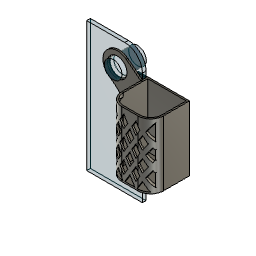
board pen holder side v5 (Autodesk Fusion 360 design; units mm, degrees)
Autodesk Fusion 360 part; units mm, degrees
sketch "Sketch1" plane through (0, 0, 0) normal (0, 1, 0) x (1, 0, 0)
  line L0 (0, 0) -> (-60, 0) construction
  line L1 (-60, 0) -> (-60, 140) construction
  line L2 (-60, 140) -> (0, 140) construction
  line L3 (0, 140) -> (0, 0) construction
  circle A0 centre (-19, 19) radius 19
  line L4 (-60, 0) -> (-19, 0)
  line L5 (0, 140) -> (0, 19)
  line L6 (-60, 0) -> (-60, 140)
  line L7 (-60, 140) -> (0, 140)
  line L8 (0, 0) -> (-34.8, 0) construction
  line L9 (-34.8, 0) -> (-34.8, 34.8) construction
  line L10 (-34.8, 34.8) -> (0, 34.8) construction
  line L11 (0, 34.8) -> (0, 0) construction
  circle A1 centre (-25.3, 25.3) radius 9.5
  dimension "d1" = 60
  dimension "d2" = 140
  dimension "d3" = 19
  dimension "d4" = 34.8
  dimension "d5" = 34.8
  dimension "d6" = 9.5
  constraint horizontal L0
  constraint vertical L1
  constraint horizontal L2
  constraint vertical L3
  constraint coincident L0.start L3.end
  constraint tangent L0 A0
  constraint tangent L3 A0
  constraint coincident A0 L4.end
  constraint tangent A0 L4
  constraint coincident A0 L5.end
  constraint tangent A0 L5
  constraint horizontal L8
  constraint vertical L9
  constraint horizontal L10
  constraint vertical L11
  constraint tangent L9 A1
  constraint tangent L10 A1
  measures "d1" distance of L0.start L0.end
  measures "d2" distance of L0.start L2.end
  measures "d3" radius of A0
  measures "d4" distance of L0.start L8.end
  measures "d5" distance of L0.start L10.end
  measures "d6" radius of A1
extrude "Extrude1" add sketch "Sketch1" along normal blind 3.95 makes body 1
extrude "Extrude2" add sketch "Sketch1" against normal blind 6.2 separate body contours A1 makes body 2
extrude "Extrude3" add sketch "Sketch1" along normal blind 20 contours A1 bodies 1 2
copy_body "Body->Comp1" bodies 1 removing the originals makes body 3 in component "Glass Board"
sketch "Sketch1 (2)" plane through (0, 0, 0) normal (0, -1, 0) x (1, 0, 0) in component "Holder"
  circle A0 centre (-25.3, -25.3) radius 9.5
  line L0 (-19, 0) -> (-60, 0)
  line L1 (-60, 0) -> (-60, -140)
  line L2 (-60, -140) -> (0, -140)
  line L3 (0, -140) -> (0, -19)
  arc A1 (0, -19) -> (-19, 0) centre (-19, -19) ccw
  circle A2 centre (-25.3, -25.3) radius 10.5
  circle A3 centre (-25.3, -25.3) radius 15.5
  line L4 (-25.3, -25.3) -> (0, -25.3) construction
  line L5 (0, -25.3) -> (-15.804, -13.0495)
  line L6 (-34.796, -37.5505) -> (-27.6206, -43.1126)
  line L7 (-16, -66.8233) -> (-16, -140) construction
  line L8 (-60, -95.3) -> (100, -95.3) construction
  line L9 (0, -25.3) -> (1.75, -25.3)
  line L10 (1.75, -25.3) -> (1.75, -95.3)
  line L11 (1.75, -95.3) -> (0, -95.3)
  line L12 (0, -95.3) -> (0, -25.3) construction
  line L13 (1.75, -25.3) -> (45, -25.3)
  line L14 (45, -25.3) -> (45, -95.3)
  line L15 (45, -95.3) -> (1.75, -95.3)
  line L16 (1.75, -95.3) -> (1.75, -25.3)
  arc A4 (-16, -66.8233) -> (-27.6206, -43.1126) centre (-46, -66.8233) ccw
  line L17 (-16, -66.8233) -> (-16, -95.3) construction
  line L18 (-16, -66.8233) -> (-16, -95.3)
  line L19 (-16, -95.3) -> (0, -95.3)
  line L20 (0, -95.3) -> (0, -25.3)
  line L21 (-16, -95.3) -> (0, -95.3)
  line L22 (0, -95.3) -> (0, -25.3)
  line L23 (0, -25.3) -> (-16, -25.3)
  line L24 (-16, -25.3) -> (-16, -95.3)
  line L25 (45, -25.3) -> (43.25, -25.3)
  line L26 (43.25, -25.3) -> (43.25, -95.3)
  line L27 (43.25, -95.3) -> (45, -95.3)
  line L28 (45, -95.3) -> (45, -25.3)
  line L29 (1.75, -95.3) -> (43.25, -95.3)
  line L30 (43.25, -95.3) -> (43.25, -93.55)
  line L31 (43.25, -93.55) -> (1.75, -93.55)
  line L32 (1.75, -93.55) -> (1.75, -95.3)
  dimension "d13" = 1
  dimension "d14" = 5
  dimension "d15" = 16
  dimension "d16" = 70
  dimension "d17" = 1.75
  dimension "d18" = 45
  dimension "d19" = 160
  dimension "d20" = 30
  dimension "d33" = 1.75
  dimension "d34" = 1.75
  constraint concentric A0 A2
  constraint concentric A2 A3
  constraint coincident A0.centre A2.centre
  constraint coincident L3 L4.end
  constraint perpendicular L3 L4
  constraint coincident A3 L5.end
  constraint tangent A3 L5
  constraint coincident A3 L6.start
  constraint parallel L5 L6
  constraint tangent A3 L6
  constraint coincident L2 L7.end
  constraint perpendicular L2 L7
  constraint coincident L1 L8.start
  constraint perpendicular L3 L8
  constraint horizontal L9
  constraint vertical L10
  constraint horizontal L11
  constraint vertical L12
  constraint coincident L8 L10.end
  constraint horizontal L13
  constraint vertical L14
  constraint horizontal L15
  constraint vertical L16
  constraint coincident L8 L14.end
  constraint tangent L6 A4
  constraint tangent L7 A4
  constraint coincident L7 L17.end
  constraint coincident L8 L17.end
  constraint horizontal L21
  constraint vertical L22
  constraint horizontal L23
  constraint vertical L24
  constraint horizontal L25
  constraint vertical L26
  constraint horizontal L27
  constraint vertical L28
  constraint coincident L8 L26.end
  constraint horizontal L29
  constraint vertical L30
  constraint horizontal L31
  constraint vertical L32
  constraint coincident L26 L30.end
  measures "d13" distance of A0 A2
  measures "d14" distance of A2 A3
  measures "d15" distance of L3 L7
  measures "d16" distance of L4.end L8
  measures "d17" distance of L10 L12
  measures "d18" distance of L3 L14
  measures "d19" distance of L8.start L8.end
  measures "d20" radius of A4
  measures "d33" distance of L26 L28
  measures "d34" distance of L29 L31
extrude "Extrude1'" add sketch "Sketch1 (2)" along normal blind 1.75 separate body contours A2 A3 L23 L24 | A2 A3 L23 L24 | L3 A3 L18 L19 L20 L21 L22 L23 L24 | A3 L5 L23 | A3 L6 A4 L24 makes body 4 in component "Holder"
extrude "Extrude2'" add sketch "Sketch1 (2)" against normal blind 1.75 from surface at -3.95 separate body contours L3 A3 L18 L19 L20 L21 L22 L23 L24 makes body 5 in component "Holder"
extrude "Extrude3'" add sketch "Sketch1 (2)" against normal up to surface (7.45 mm away) from surface at 1.75 contours L3 L9 L10 L11 L16 L20 L22 L32 bodies 4 5 in component "Holder"
extrude "Extrude4" add sketch "Sketch1 (2)" along normal blind 1.75 from surface at -5.7 contours L10 L13 L16 L26 L31 | L10 L15 L16 L26 L29 L30 L31 L32 | L13 L14 L15 L25 L26 L27 L28 L30 bodies 4 in component "Holder"
extrude "Extrude5" add sketch "Sketch1 (2)" along normal blind 40 from surface at -3.95 contours L10 L15 L16 L26 L29 L30 L31 L32 | L13 L14 L15 L25 L26 L27 L28 L30 bodies 4 in component "Holder"
extrude "Extrude6" add sketch "Sketch1 (2)" along normal up to surface (36.05 mm away) contours L3 L9 L10 L11 L16 L20 L22 L32 bodies 4 in component "Holder"
extrude "Extrude7" add sketch "Sketch1 (2)" against normal blind 1.75 from surface at 36.05 contours L10 L13 L16 L26 L31 bodies 4 in component "Holder"
sketch "Sketch2" plane through (0, -34.3, 0) normal (0, 1, 0) x (-1, 0, 0) in component "Holder"
  line L0 (-43.25, -93.55) -> (-1.75, -93.55)
  line L1 (-1.75, -93.55) -> (-1.75, -25.3)
  line L2 (-1.75, -25.3) -> (-43.25, -25.3)
  line L3 (-43.25, -25.3) -> (-43.25, -93.55)
  line L4 (-40.2857, -28.3) -> (-43.25, -34.0813) construction
  line L5 (-43.25, -34.0813) -> (-40.2857, -39.8625) construction
  line L6 (-40.2857, -39.8625) -> (-37.3214, -34.0813) construction
  line L7 (-37.3214, -34.0813) -> (-40.2857, -28.3) construction
  line L8 (-40.2857, -28.3) -> (-40.2857, -39.8625) construction
  line L9 (-43.25, -25.3) -> (-1.75, -25.3) construction
  line L10 (-1.75, -25.3) -> (-1.75, -28.3) construction
  line L11 (-1.75, -28.3) -> (-43.25, -28.3) construction
  line L12 (-43.25, -28.3) -> (-43.25, -25.3) construction
  line L13 (-43.25, -93.55) -> (-1.75, -93.55) construction
  line L14 (-1.75, -93.55) -> (-1.75, -90.55) construction
  line L15 (-1.75, -90.55) -> (-43.25, -90.55) construction
  line L16 (-43.25, -90.55) -> (-43.25, -93.55) construction
  line L17 (-64, -28.3) -> (-66.9643, -34.0813)
  line L18 (-66.9643, -34.0813) -> (-64, -39.8625)
  line L19 (-64, -39.8625) -> (-61.0357, -34.0813)
  line L20 (-61.0357, -34.0813) -> (-64, -28.3)
  line L21 (-58.0714, -28.3) -> (-61.0357, -34.0813)
  line L22 (-61.0357, -34.0813) -> (-58.0714, -39.8625)
  line L23 (-58.0714, -39.8625) -> (-55.1071, -34.0813)
  line L24 (-55.1071, -34.0813) -> (-58.0714, -28.3)
  line L25 (-52.1429, -28.3) -> (-55.1071, -34.0813)
  line L26 (-55.1071, -34.0813) -> (-52.1429, -39.8625)
  line L27 (-52.1429, -39.8625) -> (-49.1786, -34.0813)
  line L28 (-49.1786, -34.0813) -> (-52.1429, -28.3)
  line L29 (-46.2143, -28.3) -> (-49.1786, -34.0813)
  line L30 (-49.1786, -34.0813) -> (-46.2143, -39.8625)
  line L31 (-46.2143, -39.8625) -> (-43.25, -34.0813)
  line L32 (-43.25, -34.0813) -> (-46.2143, -28.3)
  line L33 (-34.3571, -28.3) -> (-37.3214, -34.0813)
  line L34 (-37.3214, -34.0813) -> (-34.3571, -39.8625)
  line L35 (-34.3571, -39.8625) -> (-31.3929, -34.0813)
  line L36 (-31.3929, -34.0813) -> (-34.3571, -28.3)
  line L37 (-28.4286, -28.3) -> (-31.3929, -34.0813)
  line L38 (-31.3929, -34.0813) -> (-28.4286, -39.8625)
  line L39 (-28.4286, -39.8625) -> (-25.4643, -34.0813)
  line L40 (-25.4643, -34.0813) -> (-28.4286, -28.3)
  line L41 (-22.5, -28.3) -> (-25.4643, -34.0813)
  line L42 (-25.4643, -34.0813) -> (-22.5, -39.8625)
  line L43 (-22.5, -39.8625) -> (-19.5357, -34.0813)
  line L44 (-19.5357, -34.0813) -> (-22.5, -28.3)
  line L45 (-64, -39.8625) -> (-66.9643, -45.6438)
  line L46 (-66.9643, -45.6438) -> (-64, -51.425)
  line L47 (-64, -51.425) -> (-61.0357, -45.6438)
  line L48 (-61.0357, -45.6438) -> (-64, -39.8625)
  line L49 (-58.0714, -39.8625) -> (-61.0357, -45.6438)
  line L50 (-61.0357, -45.6438) -> (-58.0714, -51.425)
  line L51 (-58.0714, -51.425) -> (-55.1071, -45.6438)
  line L52 (-55.1071, -45.6438) -> (-58.0714, -39.8625)
  line L53 (-52.1429, -39.8625) -> (-55.1071, -45.6438)
  line L54 (-55.1071, -45.6438) -> (-52.1429, -51.425)
  line L55 (-52.1429, -51.425) -> (-49.1786, -45.6438)
  line L56 (-49.1786, -45.6438) -> (-52.1429, -39.8625)
  line L57 (-46.2143, -39.8625) -> (-49.1786, -45.6438)
  line L58 (-49.1786, -45.6438) -> (-46.2143, -51.425)
  line L59 (-46.2143, -51.425) -> (-43.25, -45.6438)
  line L60 (-43.25, -45.6438) -> (-46.2143, -39.8625)
  line L61 (-40.2857, -39.8625) -> (-43.25, -45.6438)
  line L62 (-43.25, -45.6438) -> (-40.2857, -51.425)
  line L63 (-40.2857, -51.425) -> (-37.3214, -45.6438)
  line L64 (-37.3214, -45.6438) -> (-40.2857, -39.8625)
  line L65 (-34.3571, -39.8625) -> (-37.3214, -45.6438)
  line L66 (-37.3214, -45.6438) -> (-34.3571, -51.425)
  line L67 (-34.3571, -51.425) -> (-31.3929, -45.6438)
  line L68 (-31.3929, -45.6438) -> (-34.3571, -39.8625)
  line L69 (-28.4286, -39.8625) -> (-31.3929, -45.6438)
  line L70 (-31.3929, -45.6438) -> (-28.4286, -51.425)
  line L71 (-28.4286, -51.425) -> (-25.4643, -45.6438)
  line L72 (-25.4643, -45.6438) -> (-28.4286, -39.8625)
  line L73 (-22.5, -39.8625) -> (-25.4643, -45.6438)
  line L74 (-25.4643, -45.6438) -> (-22.5, -51.425)
  line L75 (-22.5, -51.425) -> (-19.5357, -45.6438)
  line L76 (-19.5357, -45.6438) -> (-22.5, -39.8625)
  line L77 (-64, -51.425) -> (-66.9643, -57.2063)
  line L78 (-66.9643, -57.2063) -> (-64, -62.9875)
  line L79 (-64, -62.9875) -> (-61.0357, -57.2063)
  line L80 (-61.0357, -57.2063) -> (-64, -51.425)
  line L81 (-58.0714, -51.425) -> (-61.0357, -57.2063)
  line L82 (-61.0357, -57.2063) -> (-58.0714, -62.9875)
  line L83 (-58.0714, -62.9875) -> (-55.1071, -57.2063)
  line L84 (-55.1071, -57.2063) -> (-58.0714, -51.425)
  line L85 (-52.1429, -51.425) -> (-55.1071, -57.2063)
  line L86 (-55.1071, -57.2063) -> (-52.1429, -62.9875)
  line L87 (-52.1429, -62.9875) -> (-49.1786, -57.2063)
  line L88 (-49.1786, -57.2063) -> (-52.1429, -51.425)
  line L89 (-46.2143, -51.425) -> (-49.1786, -57.2063)
  line L90 (-49.1786, -57.2063) -> (-46.2143, -62.9875)
  line L91 (-46.2143, -62.9875) -> (-43.25, -57.2063)
  line L92 (-43.25, -57.2063) -> (-46.2143, -51.425)
  line L93 (-40.2857, -51.425) -> (-43.25, -57.2063)
  line L94 (-43.25, -57.2063) -> (-40.2857, -62.9875)
  line L95 (-40.2857, -62.9875) -> (-37.3214, -57.2063)
  line L96 (-37.3214, -57.2063) -> (-40.2857, -51.425)
  line L97 (-34.3571, -51.425) -> (-37.3214, -57.2063)
  line L98 (-37.3214, -57.2063) -> (-34.3571, -62.9875)
  line L99 (-34.3571, -62.9875) -> (-31.3929, -57.2063)
  line L100 (-31.3929, -57.2063) -> (-34.3571, -51.425)
  line L101 (-28.4286, -51.425) -> (-31.3929, -57.2063)
  line L102 (-31.3929, -57.2063) -> (-28.4286, -62.9875)
  line L103 (-28.4286, -62.9875) -> (-25.4643, -57.2063)
  line L104 (-25.4643, -57.2063) -> (-28.4286, -51.425)
  line L105 (-22.5, -51.425) -> (-25.4643, -57.2063)
  line L106 (-25.4643, -57.2063) -> (-22.5, -62.9875)
  line L107 (-22.5, -62.9875) -> (-19.5357, -57.2063)
  line L108 (-19.5357, -57.2063) -> (-22.5, -51.425)
  line L109 (-64, -62.9875) -> (-66.9643, -68.7688)
  line L110 (-66.9643, -68.7688) -> (-64, -74.55)
  line L111 (-64, -74.55) -> (-61.0357, -68.7688)
  line L112 (-61.0357, -68.7688) -> (-64, -62.9875)
  line L113 (-58.0714, -62.9875) -> (-61.0357, -68.7688)
  line L114 (-61.0357, -68.7688) -> (-58.0714, -74.55)
  line L115 (-58.0714, -74.55) -> (-55.1071, -68.7688)
  line L116 (-55.1071, -68.7688) -> (-58.0714, -62.9875)
  line L117 (-52.1429, -62.9875) -> (-55.1071, -68.7688)
  line L118 (-55.1071, -68.7688) -> (-52.1429, -74.55)
  line L119 (-52.1429, -74.55) -> (-49.1786, -68.7688)
  line L120 (-49.1786, -68.7688) -> (-52.1429, -62.9875)
  line L121 (-46.2143, -62.9875) -> (-49.1786, -68.7688)
  line L122 (-49.1786, -68.7688) -> (-46.2143, -74.55)
  line L123 (-46.2143, -74.55) -> (-43.25, -68.7688)
  line L124 (-43.25, -68.7688) -> (-46.2143, -62.9875)
  line L125 (-40.2857, -62.9875) -> (-43.25, -68.7688)
  line L126 (-43.25, -68.7688) -> (-40.2857, -74.55)
  line L127 (-40.2857, -74.55) -> (-37.3214, -68.7688)
  line L128 (-37.3214, -68.7688) -> (-40.2857, -62.9875)
  line L129 (-34.3571, -62.9875) -> (-37.3214, -68.7688)
  line L130 (-37.3214, -68.7688) -> (-34.3571, -74.55)
  line L131 (-34.3571, -74.55) -> (-31.3929, -68.7688)
  line L132 (-31.3929, -68.7688) -> (-34.3571, -62.9875)
  line L133 (-28.4286, -62.9875) -> (-31.3929, -68.7688)
  line L134 (-31.3929, -68.7688) -> (-28.4286, -74.55)
  line L135 (-28.4286, -74.55) -> (-25.4643, -68.7688)
  line L136 (-25.4643, -68.7688) -> (-28.4286, -62.9875)
  line L137 (-22.5, -62.9875) -> (-25.4643, -68.7688)
  line L138 (-25.4643, -68.7688) -> (-22.5, -74.55)
  line L139 (-22.5, -74.55) -> (-19.5357, -68.7688)
  line L140 (-19.5357, -68.7688) -> (-22.5, -62.9875)
  line L141 (-64, -74.55) -> (-66.9643, -80.3313)
  line L142 (-66.9643, -80.3313) -> (-64, -86.1125)
  line L143 (-64, -86.1125) -> (-61.0357, -80.3313)
  line L144 (-61.0357, -80.3313) -> (-64, -74.55)
  line L145 (-58.0714, -74.55) -> (-61.0357, -80.3313)
  line L146 (-61.0357, -80.3313) -> (-58.0714, -86.1125)
  line L147 (-58.0714, -86.1125) -> (-55.1071, -80.3313)
  line L148 (-55.1071, -80.3313) -> (-58.0714, -74.55)
  line L149 (-52.1429, -74.55) -> (-55.1071, -80.3313)
  line L150 (-55.1071, -80.3313) -> (-52.1429, -86.1125)
  line L151 (-52.1429, -86.1125) -> (-49.1786, -80.3313)
  line L152 (-49.1786, -80.3313) -> (-52.1429, -74.55)
  line L153 (-46.2143, -74.55) -> (-49.1786, -80.3313)
  line L154 (-49.1786, -80.3313) -> (-46.2143, -86.1125)
  line L155 (-46.2143, -86.1125) -> (-43.25, -80.3313)
  line L156 (-43.25, -80.3313) -> (-46.2143, -74.55)
  line L157 (-40.2857, -74.55) -> (-43.25, -80.3313)
  line L158 (-43.25, -80.3313) -> (-40.2857, -86.1125)
  line L159 (-40.2857, -86.1125) -> (-37.3214, -80.3313)
  line L160 (-37.3214, -80.3313) -> (-40.2857, -74.55)
  line L161 (-34.3571, -74.55) -> (-37.3214, -80.3313)
  line L162 (-37.3214, -80.3313) -> (-34.3571, -86.1125)
  line L163 (-34.3571, -86.1125) -> (-31.3929, -80.3313)
  line L164 (-31.3929, -80.3313) -> (-34.3571, -74.55)
  line L165 (-28.4286, -74.55) -> (-31.3929, -80.3313)
  line L166 (-31.3929, -80.3313) -> (-28.4286, -86.1125)
  line L167 (-28.4286, -86.1125) -> (-25.4643, -80.3313)
  line L168 (-25.4643, -80.3313) -> (-28.4286, -74.55)
  line L169 (-22.5, -74.55) -> (-25.4643, -80.3313)
  line L170 (-25.4643, -80.3313) -> (-22.5, -86.1125)
  line L171 (-22.5, -86.1125) -> (-19.5357, -80.3313)
  line L172 (-19.5357, -80.3313) -> (-22.5, -74.55)
  line L173 (-43.25, -34.0813) -> (-37.3214, -34.0813) construction
  line L174 (-16.5714, -28.3) -> (-19.5357, -34.0813)
  line L175 (-19.5357, -34.0813) -> (-16.5714, -39.8625)
  line L176 (-16.5714, -39.8625) -> (-13.6071, -34.0813)
  line L177 (-13.6071, -34.0813) -> (-16.5714, -28.3)
  line L178 (-10.6429, -28.3) -> (-13.6071, -34.0813)
  line L179 (-13.6071, -34.0813) -> (-10.6429, -39.8625)
  line L180 (-10.6429, -39.8625) -> (-7.6786, -34.0813)
  line L181 (-7.6786, -34.0813) -> (-10.6429, -28.3)
  line L182 (-16.5714, -39.8625) -> (-19.5357, -45.6438)
  line L183 (-19.5357, -45.6438) -> (-16.5714, -51.425)
  line L184 (-16.5714, -51.425) -> (-13.6071, -45.6438)
  line L185 (-13.6071, -45.6438) -> (-16.5714, -39.8625)
  line L186 (-10.6429, -39.8625) -> (-13.6071, -45.6438)
  line L187 (-13.6071, -45.6438) -> (-10.6429, -51.425)
  line L188 (-10.6429, -51.425) -> (-7.6786, -45.6438)
  line L189 (-7.6786, -45.6438) -> (-10.6429, -39.8625)
  line L190 (-16.5714, -51.425) -> (-19.5357, -57.2063)
  line L191 (-19.5357, -57.2063) -> (-16.5714, -62.9875)
  line L192 (-16.5714, -62.9875) -> (-13.6071, -57.2063)
  line L193 (-13.6071, -57.2063) -> (-16.5714, -51.425)
  line L194 (-10.6429, -51.425) -> (-13.6071, -57.2063)
  line L195 (-13.6071, -57.2063) -> (-10.6429, -62.9875)
  line L196 (-10.6429, -62.9875) -> (-7.6786, -57.2063)
  line L197 (-7.6786, -57.2063) -> (-10.6429, -51.425)
  line L198 (-16.5714, -62.9875) -> (-19.5357, -68.7688)
  line L199 (-19.5357, -68.7688) -> (-16.5714, -74.55)
  line L200 (-16.5714, -74.55) -> (-13.6071, -68.7688)
  line L201 (-13.6071, -68.7688) -> (-16.5714, -62.9875)
  line L202 (-10.6429, -62.9875) -> (-13.6071, -68.7688)
  line L203 (-13.6071, -68.7688) -> (-10.6429, -74.55)
  line L204 (-10.6429, -74.55) -> (-7.6786, -68.7688)
  line L205 (-7.6786, -68.7688) -> (-10.6429, -62.9875)
  line L206 (-16.5714, -74.55) -> (-19.5357, -80.3313)
  line L207 (-19.5357, -80.3313) -> (-16.5714, -86.1125)
  line L208 (-16.5714, -86.1125) -> (-13.6071, -80.3313)
  line L209 (-13.6071, -80.3313) -> (-16.5714, -74.55)
  line L210 (-10.6429, -74.55) -> (-13.6071, -80.3313)
  line L211 (-13.6071, -80.3313) -> (-10.6429, -86.1125)
  line L212 (-10.6429, -86.1125) -> (-7.6786, -80.3313)
  line L213 (-7.6786, -80.3313) -> (-10.6429, -74.55)
  line L214 (-64, -86.1125) -> (-66.9643, -91.8938)
  line L215 (-66.9643, -91.8938) -> (-64, -97.675)
  line L216 (-64, -97.675) -> (-61.0357, -91.8938)
  line L217 (-61.0357, -91.8938) -> (-64, -86.1125)
  line L218 (-58.0714, -86.1125) -> (-61.0357, -91.8938)
  line L219 (-61.0357, -91.8938) -> (-58.0714, -97.675)
  line L220 (-58.0714, -97.675) -> (-55.1071, -91.8938)
  line L221 (-55.1071, -91.8938) -> (-58.0714, -86.1125)
  line L222 (-52.1429, -86.1125) -> (-55.1071, -91.8938)
  line L223 (-55.1071, -91.8938) -> (-52.1429, -97.675)
  line L224 (-52.1429, -97.675) -> (-49.1786, -91.8938)
  line L225 (-49.1786, -91.8938) -> (-52.1429, -86.1125)
  line L226 (-46.2143, -86.1125) -> (-49.1786, -91.8938)
  line L227 (-49.1786, -91.8938) -> (-46.2143, -97.675)
  line L228 (-46.2143, -97.675) -> (-43.25, -91.8938)
  line L229 (-43.25, -91.8938) -> (-46.2143, -86.1125)
  line L230 (-40.2857, -86.1125) -> (-43.25, -91.8938)
  line L231 (-43.25, -91.8938) -> (-40.2857, -97.675)
  line L232 (-40.2857, -97.675) -> (-37.3214, -91.8938)
  line L233 (-37.3214, -91.8938) -> (-40.2857, -86.1125)
  line L234 (-34.3571, -86.1125) -> (-37.3214, -91.8938)
  line L235 (-37.3214, -91.8938) -> (-34.3571, -97.675)
  line L236 (-34.3571, -97.675) -> (-31.3929, -91.8938)
  line L237 (-31.3929, -91.8938) -> (-34.3571, -86.1125)
  line L238 (-28.4286, -86.1125) -> (-31.3929, -91.8938)
  line L239 (-31.3929, -91.8938) -> (-28.4286, -97.675)
  line L240 (-28.4286, -97.675) -> (-25.4643, -91.8938)
  line L241 (-25.4643, -91.8938) -> (-28.4286, -86.1125)
  line L242 (-22.5, -86.1125) -> (-25.4643, -91.8938)
  line L243 (-25.4643, -91.8938) -> (-22.5, -97.675)
  line L244 (-22.5, -97.675) -> (-19.5357, -91.8938)
  line L245 (-19.5357, -91.8938) -> (-22.5, -86.1125)
  line L246 (-16.5714, -86.1125) -> (-19.5357, -91.8938)
  line L247 (-19.5357, -91.8938) -> (-16.5714, -97.675)
  line L248 (-16.5714, -97.675) -> (-13.6071, -91.8938)
  line L249 (-13.6071, -91.8938) -> (-16.5714, -86.1125)
  line L250 (-10.6429, -86.1125) -> (-13.6071, -91.8938)
  line L251 (-13.6071, -91.8938) -> (-10.6429, -97.675)
  line L252 (-10.6429, -97.675) -> (-7.6786, -91.8938)
  line L253 (-7.6786, -91.8938) -> (-10.6429, -86.1125)
  line L254 (-40.2857, -38.7666) -> (-37.8833, -34.0813)
  line L255 (-37.8833, -34.0813) -> (-40.2857, -29.3959)
  line L256 (-40.2857, -29.3959) -> (-42.6881, -34.0813)
  line L257 (-42.6881, -34.0813) -> (-40.2857, -38.7666)
  dimension "d43" = 11.5625
  dimension "d44" = 68.25
  dimension "d45" = 3
  dimension "d46" = 3
  dimension "d47" = 62.25
  dimension "d50" = 5.9286
  dimension "d51" = -11.5625
  dimension "d53" = 5.9286
  dimension "d54" = 41.5
  dimension "d55" = -0.5
  constraint parallel L5 L7
  constraint parallel L4 L6
  constraint equal L4 L7
  constraint vertical L8
  constraint horizontal L9
  constraint vertical L10
  constraint horizontal L11
  constraint vertical L12
  constraint coincident L1 L10.end
  constraint coincident L2.end L3.start
  constraint horizontal L13
  constraint vertical L14
  constraint horizontal L15
  constraint vertical L16
  constraint coincident L1 L14.end
  constraint coincident L0.start L3.end
  constraint coincident L4.start L11
  constraint coincident L3 L4.end
  measures "d43" distance of L4.start L5.end
  measures "d44" distance of L0.start L2.end
  measures "d45" distance of L2.end L11.end
  measures "d46" distance of L0.start L15.end
  measures "d47" distance of L11 L15
  measures "d53" distance of L4.end L6.end
  measures "d54" distance of L2.end L1.end
sketch "Sketch2 (2)" plane through (0, -34.3, 0) normal (0, 1, 0) x (-1, 0, 0)
  line L0 (-43.25, -93.55) -> (-1.75, -93.55)
  line L1 (-1.75, -93.55) -> (-1.75, -24.2469)
  line L2 (-1.75, -25.3) -> (-43.25, -25.3)
  line L3 (-43.25, -25.3) -> (-43.25, -93.55)
  line L4 (-43.8699, -94.5785) -> (-0.6794, -23.5392) construction
  line L5 (-42.1609, -95.6175) -> (1.0295, -24.5782)
  line L6 (-45.5788, -93.5395) -> (-2.3884, -22.5002)
  line L7 (-22.5, -25.3) -> (-22.5, -93.55) construction
  line L8 (0.5788, -93.5395) -> (-42.6116, -22.5002)
  line L9 (-2.8391, -95.6175) -> (-46.0295, -24.5782)
  line L10 (-71.5788, -93.5395) -> (-28.3884, -22.5002)
  line L11 (-68.1609, -95.6175) -> (-24.9705, -24.5782)
  line L12 (-58.5788, -93.5395) -> (-15.3884, -22.5002)
  line L13 (-55.1609, -95.6175) -> (-11.9705, -24.5782)
  line L14 (-32.5788, -93.5395) -> (10.6116, -22.5002)
  line L15 (-29.1609, -95.6175) -> (14.0295, -24.5782)
  line L16 (-19.5788, -93.5395) -> (23.6116, -22.5002)
  line L17 (-16.1609, -95.6175) -> (27.0295, -24.5782)
  line L18 (-25.4212, -93.5395) -> (-68.6116, -22.5002)
  line L19 (-28.8391, -95.6175) -> (-72.0295, -24.5782)
  line L20 (-12.4212, -93.5395) -> (-55.6116, -22.5002)
  line L21 (-15.8391, -95.6175) -> (-59.0295, -24.5782)
  line L22 (13.5788, -93.5395) -> (-29.6116, -22.5002)
  line L23 (10.1609, -95.6175) -> (-33.0295, -24.5782)
  line L24 (26.5788, -93.5395) -> (-16.6116, -22.5002)
  line L25 (23.1609, -95.6175) -> (-20.0295, -24.5782)
  line L26 (-43.25, -25.3) -> (-1.75, -25.3)
  line L27 (-1.75, -25.3) -> (-1.75, -27.3)
  line L28 (-1.75, -27.3) -> (-43.25, -27.3)
  line L29 (-43.25, -27.3) -> (-43.25, -25.3)
  point P0 (-1.75, -25.3)
  dimension "d56" = 2
  dimension "d57" = -2
  dimension "d60" = 26
  dimension "d61" = 0
  dimension "d64" = 26
  dimension "d65" = 0
  dimension "d68" = 2
  constraint midpoint L2 L7.start
  constraint midpoint L0 L7.end
  constraint symmetric L5.start L7 L9.start
  constraint symmetric L5.end L7 L9.end
  constraint symmetric L6.start L7 L8.start
  constraint symmetric L6.end L7 L8.end
  constraint coincident P0 L2.start
  constraint coincident L4 P0
  constraint horizontal L26
  constraint vertical L27
  constraint horizontal L28
  constraint vertical L29
  constraint coincident L2.end L3.start
  measures "d68" distance of L2.end L28.end
fillet "Fillet1" radius 12 2 edges at (1.75, -34.3, -59.425) (43.25, -34.3, -59.425) on bodies 4 in component "Holder"
fillet "Fillet2" radius 13.75 2 edges at (0, -36.05, -60.3) (45, -36.05, -60.3) on bodies 4 in component "Holder"
extrude "Extrude8" cut sketch "Sketch2 (2)" along normal blind 32 from surface at -20 contours L0 L5 L19 | L3 L6 L13 L19 | L0 L15 L21 | L5 L14 L18 L21 | L6 L13 L18 L21 | L0 L9 L17 | L5 L9 L14 L20 | L3 L11 L12 L18 L21 | L6 L9 L13 L20 | L9 L15 L16 L20 | L5 L8 L14 L23 | L9 L11 L12 L20 | L6 L8 L13 L23 | L1 L8 L17 L23 | L8 L15 L16 L23 | L3 L10 L20 | L5 L14 L22 L25 | L3 L9 L10 L20 | L8 L11 L12 L23 | L6 L13 L22 L25 | L1 L15 L16 L22 L25 | L1 L5 L14 L24 bodies 4 in component "Holder"
component "Glass Board" placed x (1, 0, 0) y (0, 1, 0) z (0, 0, 1) at (0, 0, 0)
component "Holder" placed x (1, 0, 0) y (0, 1, 0) z (0, 0, 1) at (0, 0, 0)
equation "d3 = ( 38 / 2 ) * 1 mm"
equation "d6 = ( 19 / 2 ) * 1 mm"
equation "d17 = wall_thickness"
equation "d21 = wall_thickness"
equation "d24 = -wall_thickness"
equation "wall_thickness = 1.75 mm"
equation "d31 = wall_thickness"
equation "d33 = wall_thickness"
equation "d34 = wall_thickness"
equation "d41 = -wall_thickness"
equation "d43 = d47 / 4 - ( 4 ) * 1 mm"
equation "d50 = d53"
equation "d53 = d54 / 7"
equation "d57 = -d56"
equation "d72 = 12 mm + 1.75 mm"
